Autodesk Fusion 360 part; units mm, degrees
(part 5 of 5)
sketch "gear (3)" plane through (0, 16.8, 0) normal (0, 1, 0) x (1, 0, 0) in component "Gripper damper gear (buy)"
  line L0 (-140.3034, 14.8533) -> (-139.9368, 14.0114)
  line L1 (-139.9368, 14.0114) -> (-139.8889, 13.7903)
  line L2 (-139.8889, 13.7903) -> (-139.8778, 13.5545)
  line L3 (-139.8778, 13.5545) -> (-139.8937, 13.3093)
  line L4 (-139.8937, 13.3093) -> (-139.9337, 13.0573)
  line L5 (-139.9337, 13.0573) -> (-139.9968, 12.8001)
  line L6 (-139.9968, 12.8001) -> (-140.082, 12.5394)
  line L7 (-140.082, 12.5394) -> (-140.5527, 12.4132)
  line L8 (-140.5527, 12.4132) -> (-140.757, 12.5962)
  line L9 (-140.757, 12.5962) -> (-140.9402, 12.7873)
  line L10 (-140.9402, 12.7873) -> (-141.1011, 12.9855)
  line L11 (-141.1011, 12.9855) -> (-141.2375, 13.1898)
  line L12 (-141.2375, 13.1898) -> (-141.3458, 13.3996)
  line L13 (-141.3458, 13.3996) -> (-141.415, 13.6149)
  line L14 (-141.415, 13.6149) -> (-141.519, 14.5273)
  line L15 (-141.519, 14.5273) -> (-141.9061, 14.501)
  line L16 (-141.9061, 14.501) -> (-142.294, 14.5102)
  line L17 (-142.294, 14.5102) -> (-142.6794, 14.5547)
  line L18 (-142.6794, 14.5547) -> (-142.8262, 13.6482)
  line L19 (-142.8262, 13.6482) -> (-142.9055, 13.4363)
  line L20 (-142.9055, 13.4363) -> (-143.0236, 13.2319)
  line L21 (-143.0236, 13.2319) -> (-143.1695, 13.0343)
  line L22 (-143.1695, 13.0343) -> (-143.3395, 12.8439)
  line L23 (-143.3395, 12.8439) -> (-143.5315, 12.6616)
  line L24 (-143.5315, 12.6616) -> (-143.7442, 12.4884)
  line L25 (-143.7442, 12.4884) -> (-144.2084, 12.6366)
  line L26 (-144.2084, 12.6366) -> (-144.2813, 12.9011)
  line L27 (-144.2813, 12.9011) -> (-144.3321, 13.1609)
  line L28 (-144.3321, 13.1609) -> (-144.3603, 13.4146)
  line L29 (-144.3603, 13.4146) -> (-144.3646, 13.6602)
  line L30 (-144.3646, 13.6602) -> (-144.3423, 13.8953)
  line L31 (-144.3423, 13.8953) -> (-144.2841, 14.1138)
  line L32 (-144.2841, 14.1138) -> (-143.8783, 14.9376)
  line L33 (-143.8783, 14.9376) -> (-144.2181, 15.1248)
  line L34 (-144.2181, 15.1248) -> (-144.5395, 15.3422)
  line L35 (-144.5395, 15.3422) -> (-144.8397, 15.588)
  line L36 (-144.8397, 15.588) -> (-145.4533, 14.9047)
  line L37 (-145.4533, 14.9047) -> (-145.6345, 14.7694)
  line L38 (-145.6345, 14.7694) -> (-145.8444, 14.6613)
  line L39 (-145.8444, 14.6613) -> (-146.074, 14.5739)
  line L40 (-146.074, 14.5739) -> (-146.3199, 14.5056)
  line L41 (-146.3199, 14.5056) -> (-146.58, 14.4561)
  line L42 (-146.58, 14.4561) -> (-146.8526, 14.4254)
  line L43 (-146.8526, 14.4254) -> (-147.1629, 14.8011)
  line L44 (-147.1629, 14.8011) -> (-147.0813, 15.0629)
  line L45 (-147.0813, 15.0629) -> (-146.9836, 15.309)
  line L46 (-146.9836, 15.309) -> (-146.8701, 15.5376)
  line L47 (-146.8701, 15.5376) -> (-146.7409, 15.7466)
  line L48 (-146.7409, 15.7466) -> (-146.5952, 15.9323)
  line L49 (-146.5952, 15.9323) -> (-146.428, 16.0847)
  line L50 (-146.428, 16.0847) -> (-145.6413, 16.5583)
  line L51 (-145.6413, 16.5583) -> (-145.826, 16.8995)
  line L52 (-145.826, 16.8995) -> (-145.9788, 17.2561)
  line L53 (-145.9788, 17.2561) -> (-146.0985, 17.6252)
  line L54 (-146.0985, 17.6252) -> (-146.984, 17.3821)
  line L55 (-146.984, 17.3821) -> (-147.2096, 17.3663)
  line L56 (-147.2096, 17.3663) -> (-147.4446, 17.3888)
  line L57 (-147.4446, 17.3888) -> (-147.685, 17.4394)
  line L58 (-147.685, 17.4394) -> (-147.9288, 17.5149)
  line L59 (-147.9288, 17.5149) -> (-148.1744, 17.6139)
  line L60 (-148.1744, 17.6139) -> (-148.4203, 17.7354)
  line L61 (-148.4203, 17.7354) -> (-148.4783, 18.2192)
  line L62 (-148.4783, 18.2192) -> (-148.268, 18.3954)
  line L63 (-148.268, 18.3954) -> (-148.0528, 18.5496)
  line L64 (-148.0528, 18.5496) -> (-147.8337, 18.6806)
  line L65 (-147.8337, 18.6806) -> (-147.6121, 18.7865)
  line L66 (-147.6121, 18.7865) -> (-147.3891, 18.8639)
  line L67 (-147.3891, 18.8639) -> (-147.1661, 18.9018)
  line L68 (-147.1661, 18.9018) -> (-146.2482, 18.8748)
  line L69 (-146.2482, 18.8748) -> (-146.2191, 19.2617)
  line L70 (-146.2191, 19.2617) -> (-146.1548, 19.6444)
  line L71 (-146.1548, 19.6444) -> (-146.056, 20.0195)
  line L72 (-146.056, 20.0195) -> (-146.9323, 20.2939)
  line L73 (-146.9323, 20.2939) -> (-147.1307, 20.4024)
  line L74 (-147.1307, 20.4024) -> (-147.3162, 20.5485)
  line L75 (-147.3162, 20.5485) -> (-147.4911, 20.721)
  line L76 (-147.4911, 20.721) -> (-147.6554, 20.9164)
  line L77 (-147.6554, 20.9164) -> (-147.8085, 21.1324)
  line L78 (-147.8085, 21.1324) -> (-147.9496, 21.3676)
  line L79 (-147.9496, 21.3676) -> (-147.7368, 21.8059)
  line L80 (-147.7368, 21.8059) -> (-147.4647, 21.8404)
  line L81 (-147.4647, 21.8404) -> (-147.2003, 21.8538)
  line L82 (-147.2003, 21.8538) -> (-146.9452, 21.8456)
  line L83 (-146.9452, 21.8456) -> (-146.7014, 21.8149)
  line L84 (-146.7014, 21.8149) -> (-146.472, 21.7594)
  line L85 (-146.472, 21.7594) -> (-146.2639, 21.6707)
  line L86 (-146.2639, 21.6707) -> (-145.5063, 21.1517)
  line L87 (-145.5063, 21.1517) -> (-145.2727, 21.4615)
  line L88 (-145.2727, 21.4615) -> (-145.0117, 21.7487)
  line L89 (-145.0117, 21.7487) -> (-144.7257, 22.0108)
  line L90 (-144.7257, 22.0108) -> (-145.3147, 22.7154)
  line L91 (-145.3147, 22.7154) -> (-145.4229, 22.914)
  line L92 (-145.4229, 22.914) -> (-145.5, 23.1371)
  line L93 (-145.5, 23.1371) -> (-145.5538, 23.3768)
  line L94 (-145.5538, 23.3768) -> (-145.5864, 23.63)
  line L95 (-145.5864, 23.63) -> (-145.5984, 23.8945)
  line L96 (-145.5984, 23.8945) -> (-145.59, 24.1687)
  line L97 (-145.59, 24.1687) -> (-145.174, 24.4224)
  line L98 (-145.174, 24.4224) -> (-144.9264, 24.3043)
  line L99 (-144.9264, 24.3043) -> (-144.6967, 24.1726)
  line L100 (-144.6967, 24.1726) -> (-144.4866, 24.0277)
  line L101 (-144.4866, 24.0277) -> (-144.2981, 23.8701)
  line L102 (-144.2981, 23.8701) -> (-144.135, 23.6994)
  line L103 (-144.135, 23.6994) -> (-144.008, 23.5123)
  line L104 (-144.008, 23.5123) -> (-143.6512, 22.6661)
  line L105 (-143.6512, 22.6661) -> (-143.2872, 22.8004)
  line L106 (-143.2872, 22.8004) -> (-142.9124, 22.9009)
  line L107 (-142.9124, 22.9009) -> (-142.5301, 22.9668)
  line L108 (-142.5301, 22.9668) -> (-142.6446, 23.878)
  line L109 (-142.6446, 23.878) -> (-142.6283, 24.1035)
  line L110 (-142.6283, 24.1035) -> (-142.5725, 24.3329)
  line L111 (-142.5725, 24.3329) -> (-142.4882, 24.5637)
  line L112 (-142.4882, 24.5637) -> (-142.3787, 24.7942)
  line L113 (-142.3787, 24.7942) -> (-142.2458, 25.0232)
  line L114 (-142.2458, 25.0232) -> (-142.0905, 25.2494)
  line L115 (-142.0905, 25.2494) -> (-141.6034, 25.2379)
  line L116 (-141.6034, 25.2379) -> (-141.459, 25.0047)
  line L117 (-141.459, 25.0047) -> (-141.337, 24.7697)
  line L118 (-141.337, 24.7697) -> (-141.2385, 24.5342)
  line L119 (-141.2385, 24.5342) -> (-141.1652, 24.2998)
  line L120 (-141.1652, 24.2998) -> (-141.1203, 24.068)
  line L121 (-141.1203, 24.068) -> (-141.1145, 23.8419)
  line L122 (-141.1145, 23.8419) -> (-141.2719, 22.9372)
  line L123 (-141.2719, 22.9372) -> (-140.893, 22.8533)
  line L124 (-140.893, 22.8533) -> (-140.5235, 22.7353)
  line L125 (-140.5235, 22.7353) -> (-140.1662, 22.584)
  line L126 (-140.1662, 22.584) -> (-139.7699, 23.4124)
  line L127 (-139.7699, 23.4124) -> (-139.6342, 23.5933)
  line L128 (-139.6342, 23.5933) -> (-139.4633, 23.7562)
  line L129 (-139.4633, 23.7562) -> (-139.2676, 23.9047)
  line L130 (-139.2676, 23.9047) -> (-139.0508, 24.0395)
  line L131 (-139.0508, 24.0395) -> (-138.8152, 24.1603)
  line L132 (-138.8152, 24.1603) -> (-138.5623, 24.2666)
  line L133 (-138.5623, 24.2666) -> (-138.1588, 23.9936)
  line L134 (-138.1588, 23.9936) -> (-138.1633, 23.7193)
  line L135 (-138.1633, 23.7193) -> (-138.1877, 23.4556)
  line L136 (-138.1877, 23.4556) -> (-138.2322, 23.2043)
  line L137 (-138.2322, 23.2043) -> (-138.2973, 22.9674)
  line L138 (-138.2973, 22.9674) -> (-138.3848, 22.7482)
  line L139 (-138.3848, 22.7482) -> (-138.5022, 22.5549)
  line L140 (-138.5022, 22.5549) -> (-139.1237, 21.8788)
  line L141 (-139.1237, 21.8788) -> (-138.8504, 21.6035)
  line L142 (-138.8504, 21.6035) -> (-138.6033, 21.3043)
  line L143 (-138.6033, 21.3043) -> (-138.3845, 20.9839)
  line L144 (-138.3845, 20.9839) -> (-137.6032, 21.4666)
  line L145 (-137.6032, 21.4666) -> (-137.3913, 21.5454)
  line L146 (-137.3913, 21.5454) -> (-137.1594, 21.59)
  line L147 (-137.1594, 21.59) -> (-136.9145, 21.6092)
  line L148 (-136.9145, 21.6092) -> (-136.6593, 21.6054)
  line L149 (-136.6593, 21.6054) -> (-136.3958, 21.5796)
  line L150 (-136.3958, 21.5796) -> (-136.1256, 21.5323)
  line L151 (-136.1256, 21.5323) -> (-135.9337, 21.0844)
  line L152 (-135.9337, 21.0844) -> (-136.0858, 20.8562)
  line L153 (-136.0858, 20.8562) -> (-136.2489, 20.6476)
  line L154 (-136.2489, 20.6476) -> (-136.4221, 20.4602)
  line L155 (-136.4221, 20.4602) -> (-136.605, 20.2961)
  line L156 (-136.605, 20.2961) -> (-136.7971, 20.1589)
  line L157 (-136.7971, 20.1589) -> (-137.0004, 20.0598)
  line L158 (-137.0004, 20.0598) -> (-137.8887, 19.8271)
  line L159 (-137.8887, 19.8271) -> (-137.8077, 19.4477)
  line L160 (-137.8077, 19.4477) -> (-137.7615, 19.0624)
  line L161 (-137.7615, 19.0624) -> (-137.7507, 18.6746)
  line L162 (-137.7507, 18.6746) -> (-136.8325, 18.6583)
  line L163 (-136.8325, 18.6583) -> (-136.6116, 18.61)
  line L164 (-136.6116, 18.61) -> (-136.3924, 18.5221)
  line L165 (-136.3924, 18.5221) -> (-136.176, 18.4059)
  line L166 (-136.176, 18.4059) -> (-135.9634, 18.2647)
  line L167 (-135.9634, 18.2647) -> (-135.7556, 18.1005)
  line L168 (-135.7556, 18.1005) -> (-135.5539, 17.9147)
  line L169 (-135.5539, 17.9147) -> (-135.6346, 17.4341)
  line L170 (-135.6346, 17.4341) -> (-135.886, 17.3243)
  line L171 (-135.886, 17.3243) -> (-136.1359, 17.237)
  line L172 (-136.1359, 17.237) -> (-136.383, 17.1731)
  line L173 (-136.383, 17.1731) -> (-136.6255, 17.1338)
  line L174 (-136.6255, 17.1338) -> (-136.8613, 17.1224)
  line L175 (-136.8613, 17.1224) -> (-137.0859, 17.1489)
  line L176 (-137.0859, 17.1489) -> (-137.9591, 17.4334)
  line L177 (-137.9591, 17.4334) -> (-138.096, 17.0704)
  line L178 (-138.096, 17.0704) -> (-138.2654, 16.7213)
  line L179 (-138.2654, 16.7213) -> (-138.466, 16.3892)
  line L180 (-138.466, 16.3892) -> (-137.7024, 15.8791)
  line L181 (-137.7024, 15.8791) -> (-137.5427, 15.719)
  line L182 (-137.5427, 15.719) -> (-137.4058, 15.5266)
  line L183 (-137.4058, 15.5266) -> (-137.2866, 15.3118)
  line L184 (-137.2866, 15.3118) -> (-137.184, 15.0781)
  line L185 (-137.184, 15.0781) -> (-137.098, 14.8277)
  line L186 (-137.098, 14.8277) -> (-137.0288, 14.5622)
  line L187 (-137.0288, 14.5622) -> (-137.3565, 14.2016)
  line L188 (-137.3565, 14.2016) -> (-137.6273, 14.2452)
  line L189 (-137.6273, 14.2452) -> (-137.8848, 14.3069)
  line L190 (-137.8848, 14.3069) -> (-138.1272, 14.3866)
  line L191 (-138.1272, 14.3866) -> (-138.3525, 14.4847)
  line L192 (-138.3525, 14.4847) -> (-138.557, 14.6026)
  line L193 (-138.557, 14.6026) -> (-138.7317, 14.7463)
  line L194 (-138.7317, 14.7463) -> (-139.3124, 15.4577)
  line L195 (-139.3124, 15.4577) -> (-139.6238, 15.2263)
  line L196 (-139.6238, 15.2263) -> (-139.9551, 15.0243)
  line L197 (-139.9551, 15.0243) -> (-140.3034, 14.8533)
extrude "gear (1)''" add sketch "gear (3)" along normal blind 3 separate body makes body 120 in component "Gripper damper gear (buy)"
ref_plane "WorkPlane2" through (0, 19.79, 0) normal (0, 1, 0) x (0, 0, 1) in component "Gripper damper gear (buy)"
sketch "shaft" plane through (0, 19.79, 0) normal (0, 1, 0) x (1, 0, 0) in component "Gripper damper gear (buy)"
  circle A0 centre (-142, 18.75) radius 1.5
extrude "shaft (1)" add sketch "shaft" along normal blind 0.72 separate body makes body 121 in component "Gripper damper gear (buy)"
combine "Combine1'''''''''" operation add target body 120 tool bodies 121 in component "Gripper damper gear (buy)"
ref_plane "WorkPlane7" through (0, 20.5, 0) normal (0, 1, 0) x (0, 0, 1) in component "Gripper HW head (buy)"
sketch "damper body" plane through (0, 20.5, 0) normal (0, 1, 0) x (1, 0, 0) in component "Gripper HW head (buy)"
  circle A0 centre (-142, 18.75) radius 7
extrude "damper body (1)" add sketch "damper body" along normal blind 3.5 separate body makes body 122 in component "Gripper HW head (buy)"
ref_plane "WorkPlane1" through (0, 25, 0) normal (0, 1, 0) x (0, 0, 1) in component "Gripper HW drive pin (buy)"
sketch "M4 x 20 socket head, drive pin (buy)" plane through (0, 25, 0) normal (0, 1, 0) x (1, 0, 0) in component "Gripper HW drive pin (buy)"
  circle A0 centre (-136, -37.5) radius 3.5
extrude "M4 x 20 socket head, drive pin (buy) (1)" add sketch "M4 x 20 socket head, drive pin (buy)" along normal blind 4 separate body makes body 123 in component "Gripper HW drive pin (buy)"
ref_plane "WorkPlane2" through (0, 29, 0) normal (0, 1, 0) x (0, 0, 1) in component "Gripper HW drive pin (buy)"
sketch "M4 x 20 socket head, drive pin (buy) shank" plane through (0, 29, 0) normal (0, 1, 0) x (1, 0, 0) in component "Gripper HW drive pin (buy)"
  circle A0 centre (-136, -37.5) radius 2
extrude "M4 x 20 socket head, drive pin (buy) shank (1)" add sketch "M4 x 20 socket head, drive pin (buy) shank" along normal blind 20 bodies 123 in component "Gripper HW drive pin (buy)"
ref_plane "WorkPlane3" through (0, 45.4, 0) normal (0, 1, 0) x (0, 0, 1) in component "Gripper HW drive pin (buy)"
sketch "nut" plane through (0, 45.4, 0) normal (0, 1, 0) x (1, 0, 0) in component "Gripper HW drive pin (buy)"
  line L0 (-133.9793, -41) -> (-131.9585, -37.5)
  line L1 (-131.9585, -37.5) -> (-133.9793, -34)
  line L2 (-133.9793, -34) -> (-138.0207, -34)
  line L3 (-138.0207, -34) -> (-140.0415, -37.5)
  line L4 (-140.0415, -37.5) -> (-138.0207, -41)
  line L5 (-138.0207, -41) -> (-133.9793, -41)
extrude "nut (1)" add sketch "nut" along normal blind 3.2 separate body makes body 124 in component "Gripper HW drive pin (buy)"
ref_plane "WorkPlane4" through (0, 44.4, 0) normal (0, 1, 0) x (0, 0, 1) in component "Gripper HW drive pin (buy)"
sketch "thread" plane through (0, 44.4, 0) normal (0, 1, 0) x (1, 0, 0) in component "Gripper HW drive pin (buy)"
  circle A0 centre (-136, -37.5) radius 2
extrude "thread (1)" cut sketch "thread" along normal blind 6 bodies 124 in component "Gripper HW drive pin (buy)"
sketch "paths (2)" plane through (0, 0, 0) normal (0, 0, 1) x (1, 0, 0) in component "Gripper HW head (buy)"
  line L0 (-131.4, 36, 36.5) -> (-127, 36, 29.5)
pipe "closing spring" add diameter 3.2 path "paths (2)" along L0 separate body makes body 125 in component "Gripper HW head (buy)"
component "CDX-3R shoulder + back" placed x (1, 0, 0) y (0, 0, 1) z (0, -1, 0) at (0, 0, 0)
component "Gripper (prototype 2)" placed x (0.987598, 0.140113, -0.070845) y (0.156681, -0.850536, 0.502036) z (0.010085, -0.50691, -0.86194) at (218.9775, 1074.0619, 327.1942) in component "CDX-3R shoulder + back"
component "Gripper rail base (printed)" placed x (1, 0, 0) y (0, 1, 0) z (0, 0, 1) at (0, 0, 0) in component "Gripper (prototype 2)"
component "Gripper rail MGN12 (buy)" placed x (1, 0, 0) y (0, 1, 0) z (0, 0, 1) at (0, 0, 0) in component "Gripper (prototype 2)"
component "Gripper carriage MGN12H (buy)" placed x (1, 0, 0) y (0, 1, 0) z (0, 0, 1) at (0, 0, 0) in component "Gripper (prototype 2)"
component "Gripper finger R (TPU)" placed x (1, 0, 0) y (0, 1, 0) z (0, 0, 1) at (0, 0, 0) in component "Gripper (prototype 2)"
component "Gripper finger L (TPU)" placed x (1, 0, 0) y (0, 1, 0) z (0, 0, 1) at (0, 0, 0) in component "Gripper (prototype 2)"
component "Gripper head plate (printed)" placed x (1, 0, 0) y (0, 1, 0) z (0, 0, 1) at (0, 0, 0) in component "Gripper (prototype 2)"
component "Gripper head lid (printed)" placed x (1, 0, 0) y (0, 1, 0) z (0, 0, 1) at (0, 0, 0) in component "Gripper (prototype 2)"
component "Gripper gear R (printed)" placed x (1, 0, 0) y (0, 1, 0) z (0, 0, 1) at (0, 0, 0) in component "Gripper (prototype 2)"
component "Gripper gear L (printed)" placed x (1, 0, 0) y (0, 1, 0) z (0, 0, 1) at (0, 0, 0) in component "Gripper (prototype 2)"
component "Gripper trigger (printed)" placed x (1, 0, 0) y (0, 1, 0) z (0, 0, 1) at (0, 0, 0) in component "Gripper (prototype 2)"
component "Gripper pusher (printed)" placed x (1, 0, 0) y (0, 1, 0) z (0, 0, 1) at (0, 0, 0) in component "Gripper (prototype 2)"
component "Gripper handle (printed)" placed x (1, 0, 0) y (0, 1, 0) z (0, 0, 1) at (0, 0, 0) in component "Gripper (prototype 2)"
component "Gripper HW fixed (buy)" placed x (1, 0, 0) y (0, 1, 0) z (0, 0, 1) at (0, 0, 0) in component "Gripper (prototype 2)"
component "Gripper HW head (buy)" placed x (1, 0, 0) y (0, 1, 0) z (0, 0, 1) at (0, 0, 0) in component "Gripper (prototype 2)"
component "Gripper spool (printed)" placed x (1, 0, 0) y (0, 1, 0) z (0, 0, 1) at (0, 0, 0) in component "Gripper (prototype 2)"
component "Gripper HW trigger nipple (buy)" placed x (1, 0, 0) y (0, 1, 0) z (0, 0, 1) at (0, 0, 0) in component "Gripper (prototype 2)"
component "Gripper HW pusher nipple (buy)" placed x (1, 0, 0) y (0, 1, 0) z (0, 0, 1) at (0, 0, 0) in component "Gripper (prototype 2)"
component "Gripper HW finger R (buy)" placed x (1, 0, 0) y (0, 1, 0) z (0, 0, 1) at (0, 0, 0) in component "Gripper (prototype 2)"
component "Gripper HW finger L (buy)" placed x (1, 0, 0) y (0, 1, 0) z (0, 0, 1) at (0, 0, 0) in component "Gripper (prototype 2)"
component "Gripper damper gear (buy)" placed x (1, 0, 0) y (0, 1, 0) z (0, 0, 1) at (0, 0, 0) in component "Gripper (prototype 2)"
component "Gripper HW drive pin (buy)" placed x (1, 0, 0) y (0, 1, 0) z (0, 0, 1) at (0, 0, 0) in component "Gripper (prototype 2)"
equation "d7085 = -( 2.40 mm )"
equation "d7089 = -( 9.50 mm )"
equation "d7091 = -( 2.40 mm )"
equation "d7093 = -( 9.50 mm )"
equation "d7097 = -( 2.40 mm )"
equation "d7101 = -( 9.50 mm )"
equation "d7105 = -( 3.00 mm )"
equation "d7109 = -( 8.00 mm )"
equation "d7115 = -( 3.00 mm )"
equation "d7117 = -( 8.00 mm )"
equation "d7121 = -( 3.00 mm )"
equation "d7123 = -( 8.00 mm )"
equation "d7127 = -( 3.00 mm )"
equation "d7129 = -( 8.00 mm )"
equation "d7133 = -( 3.00 mm )"
equation "d7135 = -( 8.00 mm )"
equation "d7139 = -( 3.00 mm )"
equation "d7141 = -( 8.00 mm )"
equation "d7147 = -( 3.00 mm )"
equation "d7151 = -( 8.00 mm )"
equation "d7159 = -( 3.00 mm )"
equation "d7163 = -( 8.00 mm )"
equation "d7169 = -( 3.00 mm )"
equation "d7171 = -( 8.00 mm )"
equation "d7193 = -( 3.00 mm )"
equation "d7197 = -( 10.00 mm )"
equation "d7353 = -( 3.00 mm )"
equation "d7357 = -( 16.00 mm )"
equation "d7363 = -( 3.00 mm )"
equation "d7365 = -( 16.00 mm )"
equation "d7369 = -( 3.00 mm )"
equation "d7371 = -( 8.00 mm )"
equation "d7377 = -( 3.00 mm )"
equation "d7379 = -( 8.00 mm )"
equation "d7385 = -( 3.00 mm )"
equation "d7389 = -( 8.00 mm )"
equation "d7391 = -( 3.00 mm )"
equation "d7393 = -( 8.00 mm )"
equation "d7395 = -( 3.00 mm )"
equation "d7397 = -( 8.00 mm )"
equation "d7399 = -( 3.00 mm )"
equation "d7401 = -( 8.00 mm )"
equation "d7405 = -( 3.00 mm )"
equation "d7409 = -( 16.00 mm )"
equation "d7417 = -( 3.00 mm )"
equation "d7421 = -( 16.00 mm )"
named bodies: "rail base (printed)", "MGN12 linear rail, 300 mm (buy)", "MGN12H carriage, M3 threaded holes (buy)", "fin-ray finger R (TPU)", "fin-ray finger L (TPU)", "head plate (printed)", "head lid (printed)", "gear R + drive arm, m1 z19 (printed)", "gear L, m1 z19 (printed)", "trigger (printed)", "pusher lever (printed)", "handle (printed)", "#4 x 3/8  pan-head self-tapping screw, pipe (buy)", "#4 x 3/8  pan-head self-tapping screw, pipe (buy) (1)", "#4 x 3/8  pan-head self-tapping screw, ring (buy)", "M3 x 8 socket head, rail (buy)", "M3 heat-set insert ruthex 5.7, rail (buy)", "M3 x 8 socket head, rail (buy) (1)", "M3 heat-set insert ruthex 5.7, rail (buy) (1)", "M3 x 8 socket head, rail (buy) (2)", "M3 heat-set insert ruthex 5.7, rail (buy) (2)", "M3 x 8 socket head, rail (buy) (3)", "M3 heat-set insert ruthex 5.7, rail (buy) (3)", "M3 x 8 socket head, rail (buy) (4)", "M3 heat-set insert ruthex 5.7, rail (buy) (4)", "M3 x 8 socket head, rail (buy) (5)", "M3 heat-set insert ruthex 5.7, rail (buy) (5)", "M3 x 8 socket head, spool (buy)", "M3 heat-set insert ruthex 5.7, spool (buy)", "M3 x 8 socket head, handle flange (buy)", "M3 heat-set insert ruthex 5.7, handle flange (buy)", "M3 x 8 socket head, handle flange (buy) (1)", "M3 heat-set insert ruthex 5.7, handle flange (buy) (1)", "spool (printed): the constant-force spring coils on it", "constant-force spring ~3 N, 6 mm wide (buy)", "constant-force spring tape (buy)", "M3 x 10 socket head, pusher pivot (buy)", "M3 heat-set insert ruthex 5.7, pusher (buy)", "index plunger M8, pull knob, pin 5 mm (buy)", "M3 x 40 socket head, trigger pivot (buy)", "brake cable housing 5 mm (buy)", "brake cable inner wire 1.5 mm (buy)", "brake cable barrel nipple 6 x 6 (buy, on the wire)", "solderless screw nipple 6.5 x 8 (buy): clamps the wire, sets the tension", "M3 x 16 socket head, gear axle (buy)", "M3 heat-set insert ruthex 5.7, gear axle (buy)", "M3 x 16 socket head, gear axle (buy) (1)", "M3 heat-set insert ruthex 5.7, gear axle (buy) (1)", "M3 x 8 socket head, lid (buy)", "M3 heat-set insert ruthex 5.7, lid (buy)", "M3 x 8 socket head, lid (buy) (1)", "M3 heat-set insert ruthex 5.7, lid (buy) (1)", "M3 x 8 socket head, carriage (buy)", "M3 x 8 socket head, carriage (buy) (1)", "M3 x 8 socket head, carriage (buy) (2)", "M3 x 8 socket head, carriage (buy) (3)", "M3 x 16 socket head, finger (buy)", "M3 heat-set insert ruthex 5.7, finger (buy)", "damper gear 11T m1 + shaft (buy, part of the rotary damper)", "rotary gear damper, body (buy)"
